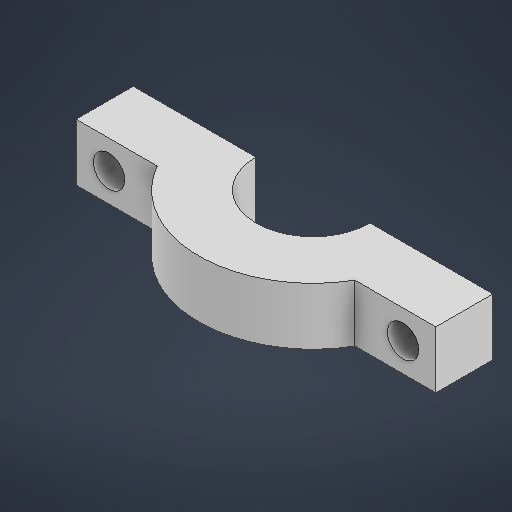
# Autodesk Inventor part: 2_07_attache_support_servomot
Saved by Autodesk Inventor 2026 (Build 300175000, 175)
## iProperties
Created: 2025-06-07
Part Number: 2_07_attache_support_servomot
Material: Générique
Document SubType Name: Modeling
Designer: Diogo
Density: 1 g/cm^3
Appearance: Par défaut
Author: Diogo
Autodesk Inventor part; units mm, degrees
ref_plane "YZ Plane" through (0, 0, 0) normal (1, 0, 0) x (0, 1, 0)
ref_plane "XZ Plane" through (0, 0, 0) normal (0, 1, 0) x (-1, 0, 0)
ref_plane "XY Plane" through (0, 0, 0) normal (0, 0, 1) x (1, 0, 0)
sketch "Esquisse1" plane through (0, 0, 0) normal (0, 1, 0) x (-1, 0, 0)
  line L0 (0, 0) -> (21.5, 0)
  line L1 (53.9644, 0) -> (-47.7649, 0) construction
  arc A0 (41.5, 0) -> (21.5, 0) centre (31.5, 0) ccw
  arc A1 (48.8205, 10) -> (14.1795, 10) centre (31.5, 0) ccw
  line L2 (0, 0) -> (0, 10)
  line L3 (0, 10) -> (14.1795, 10)
  line L4 (41.5, 0) -> (63, 0)
  line L5 (63, 0) -> (63, 10)
  line L6 (63, 10) -> (48.8205, 10)
  dimension "d0" = 21.5
  dimension "d1" = 20
  dimension "d2" = 40
  dimension "d3" = 10
  dimension "d4" = 21.5
  dimension "d5" = 10
  constraints: 14 end point, 4 point on circle, 4 point on line, 3 horizontal, 3 perpendicular, 2 centre point, 1 coincident, 1 vertical
  measures "d0" distance of L0.end L0.start
  measures "d1" diameter of A0
  measures "d2" diameter of A1
  measures "d3" distance of L0.start L2.end
  measures "d4" distance of L4.start L4.end
  measures "d5" distance of L4.end L5.end
extrude "Extrusion1" add sketch "Esquisse1" along normal blind 10
sketch "Esquisse2" plane through (-63, 0, 10) normal (0, 0, 1) x (1, 0, 0)
  line L0 (0, 0) -> (0, 10) projected
  line L1 (0, 10) -> (14.1795, 10) projected
  point P0 (63, 0)
  point P1 (5.75, 5)
  dimension "d8" = 5.75
  dimension "d9" = 5
  measures "d8" distance from line of L0 point (5.75, 5)
  measures "d9" distance from line of L1 point (5.75, 5)
hole "Perçage1" at (-57.25, 5, 10) direction (0, 0, -1) diameter 5.5 end through all
pattern_linear "Réseau rectangulaire1" count 2 spacing 51.5 along (1, 0, 0) of "Perçage1"
